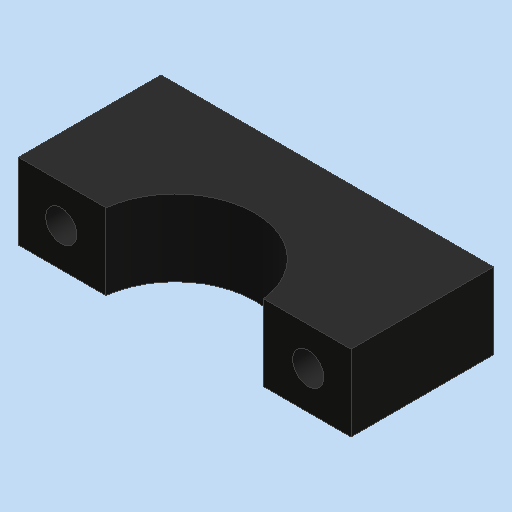
# Autodesk Inventor part: MM0948AN002_G01_103
Saved by Autodesk Inventor 2023.3 (Build 273359000, 359)
## iProperties
Created: 2023-03-23
Part Number: MM0948AN002_G01_103
Material: Kst - Pa 66 GF30  (schwarz)
Description: =<RBPARTNOTITLE2>
Document SubType Name: Modeling
Designer: ric7an
Mass: 33.4491 g
Surface Area: 81.9706 cm^2
Volume: 24.7771 cm^3
Density: 1.35 g/cm^3
Appearance: schwarz AnP
AnP_Kategorie: 1
AnP_Material: =<Material>
MaxAbmaße: 16 x 30 x 70 (FM)
AnP_TemplVers: 20200821
RBDOCUMENTTYPE: DRF
RBDOCUMENTVERSION: 00
RBDRAWINGMAINSCALE: 1:1
RBDRAWINGMISSINGSPEC: --
RBDRAWINGVOLUME: --
RBDSV1: 0850
RBGBEDGESIN1: +0,5
RBGBEDGESIN2: +0,2
RBGBEDGESOUT1: -0,3
RBGBEDGESOUT2: -0,1
RBGBREMARKSINDEX: E
RBMATERIAL: =<Material>
RBMATMEETS: --
RBMATNO: =<Part Number>
RBPARTMADEOF: 16 x 30 x 70 (FM)
RBPARTNO: SIEHE MNR
RBPARTNOTITLE1: manufactured part
RBPARTNOTITLE2: Anfertigungsteil
RBPARTSAFETYINDICATOR: --
RBSURFACE: --
RBSURFACE2: --
RBZEDGESNORM: ISO13715:2002-06
RBZGENDIMCLASS: m
RBZGENDIMNORM: ISO 2768-1:1989-11
RBZGENGEOCLASS: H
RBZGENGEONORM: ISO 2768-2:1989-11
RBZSURFACENORM: ISO13D2:2002-02
RBZTOLERANCENORM: ISO 14405-1:2010-12
AnP_Kommentar_aktuell: =<Comments>
AnP_Material_aktuell: =<Material>
Author: FH/Wi
Keywords: =<RBPARTMADEOF>
Comments: =<RBSURFACE2>
Revision Number: 01
Autodesk Inventor part; units mm, degrees
ref_plane "YZ Plane" through (0, 0, 0) normal (1, 0, 0) x (0, 1, 0)
ref_plane "XZ Plane" through (0, 0, 0) normal (0, 1, 0) x (-1, 0, 0)
ref_plane "XY Plane" through (0, 0, 0) normal (0, 0, 1) x (1, 0, 0)
sketch "Skizze1" plane through (0, 0, 0) normal (0, 0, 1) x (1, 0, 0)
  line L0 (-35, 30) -> (35, 30)
  line L1 (35, 30) -> (35, 0)
  line L2 (35, 0) -> (-35, 0)
  line L3 (-35, 0) -> (-35, 30)
  line L4 (0, 39.74) -> (0, -28.44) projected
  line L5 (-49, 0) -> (49, 0) projected
  circle A0 centre (0, -2) radius 16.7
  point P0 (-16.5798, 0)
  point P1 (16.5798, 0)
  dimension "d0" = 33.4
  dimension "d1" = 70
  dimension "d2" = 30
  dimension "d3" = 2
  constraints: 8 end point, 2 horizontal, 2 parallel, 1 centre point, 1 coincident, 1 perpendicular, 1 point on line, 2 other
  measures "d0" diameter of A0
  measures "d1" distance of L0.start L0.end
  measures "d2" distance of L0.end L1.end
  measures "d3" distance from line of point (0, -2) L2
extrude "Extrusion1" add sketch "Skizze1" along normal mid plane 16 contours L0 L4 A0 L2 L3 | L0 L1 L2 A0 L4
sketch "Skizze2" plane through (-35, 30, 8) normal (0, 1, 0) x (1, 0, 0)
  line L0 (35, 19.2) -> (35, -3.2) projected
  line L1 (84, 8) -> (-14, 8) projected
  point P0 (35, 8)
  point P1 (9, 8)
  point P2 (61, 8)
  dimension "d6" = 52
  constraints: 1 point on line, 1 symmetric about line
  measures "d6" distance of point (61, 8) point (9, 8)
hole "Bohrung1" at (-26, 30, 0) at (26, 30, 0) direction (0, -1, 0) diameter 6.6 end through all counterbore diameter 11 counterbore depth 6.8 clearance for "Inbusschraube ISO 4762  versenkt" size "M6" standard "ISO"
